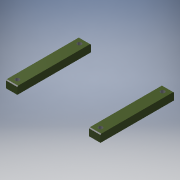
# Autodesk Inventor part: largueros
Saved by Autodesk Inventor 2017 (Build 210142000, 142)
## iProperties
Part Number: largueros
Material: Genérico
Document SubType Name: Modeling
Designer: HP Pav
Density: 1 g/cm^3
Appearance: Valor por defecto
Author: HP Pav
Autodesk Inventor part; units mm, degrees
ref_plane "YZ Plane" through (0, 0, 0) normal (1, 0, 0) x (0, 1, 0)
ref_plane "XZ Plane" through (0, 0, 0) normal (0, 1, 0) x (-1, 0, 0)
ref_plane "XY Plane" through (0, 0, 0) normal (0, 0, 1) x (1, 0, 0)
sketch "Boceto1" plane through (0, 0, 0) normal (0, 0, 1) x (1, 0, 0)
  line L0 (-125, 97.25) -> (-125, -97.25) projected
  circle A0 centre (-110, 82.25) radius 5.5 projected
  circle A1 centre (-110, -82.25) radius 5.5 projected
  line L1 (125, -97.25) -> (125, 97.25) projected
  circle A2 centre (110, -82.25) radius 5.5 projected
  circle A3 centre (110, 82.25) radius 5.5 projected
  line L2 (-125, -97.25) -> (-95, -97.25)
  line L3 (-95, -97.25) -> (-95, 97.25)
  line L4 (-95, 97.25) -> (-125, 97.25)
  line L5 (125, 97.25) -> (95, 97.25)
  line L6 (95, 97.25) -> (95, -97.25)
  line L7 (95, -97.25) -> (125, -97.25)
  point P0 (0, 0)
  dimension "d0" = 30
  dimension "d1" = 30
  constraints: 12 end point, 4 perpendicular, 2 horizontal
  measures "d0" distance of L3.end L0.start
  measures "d1" distance of L1.end L5.end
extrude "Extrusión1" add sketch "Boceto1" along normal blind 20
chamfer "Chaflán1" distance 2 angle 45 1 edges at (110, -97.25, 20)
chamfer "Chaflán2" distance 2 angle 45 1 edges at (-110, -97.25, 20)
chamfer "Chaflán3" distance 2 angle 45 1 edges at (-110, 97.25, 20)
chamfer "Chaflán4" distance 2 angle 45 1 edges at (110, 97.25, 20)
